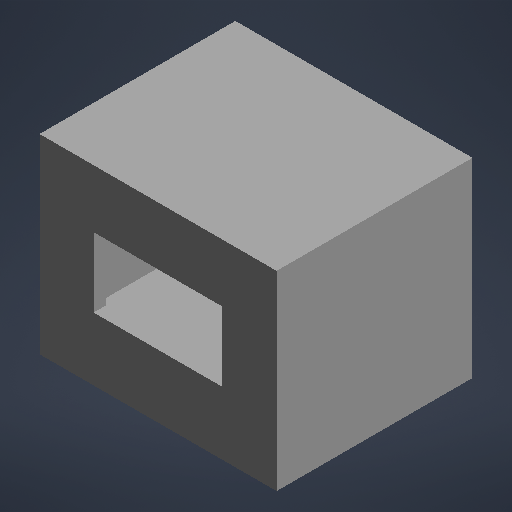
# Autodesk Inventor part: R2_cabeza
Saved by Autodesk Inventor 2027 (Build 310192060, 192F)
## iProperties
Part Number: R2_cabeza
Material: Genérico
Document SubType Name: Modelado
Designer: rodri
Appearance: Por defecto
Author: rodri
Autodesk Inventor part; units mm, degrees
ref_plane "Plano de trabajo1" through (0, 0, -15) normal (0, 0, 1) x (1, 0, 0)
sketch "Boceto1" plane through (0, 0, -15) normal (0, 0, 1) x (1, 0, 0)
  line L0 (-23, 80) -> (23, 80)
  line L1 (23, 80) -> (23, 117)
  line L2 (23, 117) -> (-23, 117)
  line L3 (-23, 117) -> (-23, 80)
  constraints: 8 end point, 2 parallel, 1 horizontal, 1 perpendicular
extrude "Extrusión1" add sketch "Boceto1" along normal blind 38
ref_plane "Plano de trabajo2" through (0, 0, -12.6) normal (0, 0, 1) x (1, 0, 0)
sketch "Boceto2" plane through (0, 0, -12.6) normal (0, 0, 1) x (1, 0, 0)
  line L0 (-20.6, 85.4) -> (20.6, 85.4)
  line L1 (20.6, 85.4) -> (20.6, 114.6)
  line L2 (20.6, 114.6) -> (-20.6, 114.6)
  line L3 (-20.6, 114.6) -> (-20.6, 85.4)
  constraints: 8 end point, 2 parallel, 1 horizontal, 1 perpendicular
extrude "Extrusión2" cut sketch "Boceto2" along normal blind 33.2
ref_plane "Plano de trabajo3" through (0, 0, 20.5) normal (0, 0, 1) x (1, 0, 0)
sketch "Boceto3" plane through (0, 0, 20.5) normal (0, 0, 1) x (1, 0, 0)
  line L0 (-12.5, 92.25) -> (12.5, 92.25)
  line L1 (12.5, 92.25) -> (12.5, 105.75)
  line L2 (12.5, 105.75) -> (-12.5, 105.75)
  line L3 (-12.5, 105.75) -> (-12.5, 92.25)
  constraints: 8 end point, 2 parallel, 1 horizontal, 1 perpendicular
extrude "Extrusión3" cut sketch "Boceto3" along normal blind 2.6
